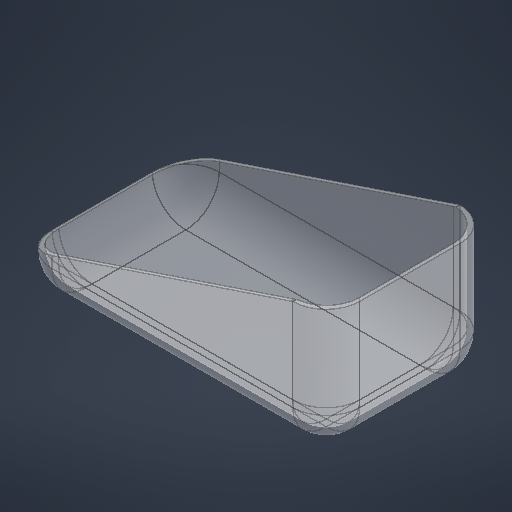
# Autodesk Inventor part: box
Saved by Autodesk Inventor 2026.2 (Build 302298010, 298A)
## iProperties
Created: 2026-04-03
Part Number: box
Material: ABS 플라스틱
Document SubType Name: Modeling
Designer: work
Density: 1.06 g/cm^3
Appearance: 선명 - 밝음
Author: work
Autodesk Inventor part; units mm, degrees
ref_plane "YZ Plane" through (0, 0, 0) normal (1, 0, 0) x (0, 1, 0)
ref_plane "XZ Plane" through (0, 0, 0) normal (0, 1, 0) x (-1, 0, 0)
ref_plane "XY Plane" through (0, 0, 0) normal (0, 0, 1) x (1, 0, 0)
sketch "스케치1" plane through (0, 0, 0) normal (1, 0, 0) x (0, 1, 0)
  line L0 (0, 0) -> (75, 0)
  line L1 (75, 0) -> (75, -100)
  line L2 (75, -100) -> (0, -100)
  line L3 (0, -100) -> (0, 0)
  line L4 (75, -2) -> (2, -2)
  line L5 (2, -2) -> (2, -98)
  line L6 (2, -98) -> (75, -98)
  line L7 (75, -98) -> (75, -2)
  point P0 (75, -50)
  point P1 (75, -98)
  dimension "d0" = 75
  dimension "d1" = 100
  dimension "d2" = 2
  dimension "d3" = 2
  constraints: 16 end point, 4 parallel, 2 horizontal, 2 midpoint, 2 perpendicular, 1 point on line
  measures "d0" distance of L1.end L2.end
  measures "d1" distance of L0.end L1.end
  measures "d2" distance between parallel lines of L0 L4
  measures "d3" distance between parallel lines of L3 L5
extrude "돌출1" add sketch "스케치1" along normal blind 180 contours L0 L1 L4 L5 L6 L2 L3
sketch "스케치2" plane through (0, 0, 0) normal (-1, 0, 0) x (0, 0, 1)
  line L0 (0, 0) -> (-100, 0) projected
  line L1 (-2, 75) -> (0, 75) projected
  line L2 (-100, 0) -> (0, 0)
  line L3 (0, 0) -> (0, 75)
  line L4 (0, 75) -> (-100, 75)
  line L5 (-100, 75) -> (-100, 0)
  constraints: 8 end point, 2 parallel, 1 horizontal, 1 perpendicular
extrude "돌출2" add sketch "스케치2" along normal blind 2
sketch "스케치3" plane through (180, 0, 0) normal (1, 0, 0) x (0, 0, -1)
  line L0 (100, 75) -> (100, 0) projected
  line L1 (0, 0) -> (100, 0)
  line L2 (100, 0) -> (100, 75)
  line L3 (100, 75) -> (0, 75)
  line L4 (0, 75) -> (0, 0)
  constraints: 8 end point, 2 parallel, 1 horizontal, 1 perpendicular
extrude "돌출3" add sketch "스케치3" along normal blind 2
fillet "모깎기1" radius 20 8 edges at (182, 37.5, 0) (180, 38.5, -2) (0, 38.5, -2) (0, 38.5, -98) (-2, 37.5, -100) (180, 38.5, -98) (182, 37.5, -100) (-2, 37.5, 0)
fillet "모깎기2" radius 20 16 edges at (174.1421, 2, -7.8579) (180, 2, -50) (174.1421, 2, -92.1421) (90, 2, -98) (5.8579, 2, -92.1421) (0, 2, -50) (5.8579, 2, -7.8579) (90, 2, -2) (176.1421, 0, -94.1421) (90, 0, -100) (3.8579, 0, -94.1421) (-2, 0, -50) (3.8579, 0, -5.8579) (90, 0, 0) (176.1421, 0, -5.8579) (182, 0, -50)
sketch "스케치4" plane through (162, 75, -100) normal (0, 0, -1) x (-1, 0, 0)
  line L0 (2, 0) -> (-18, 0) projected
  line L1 (164, 0) -> (164, -55) projected
  line L2 (-0.0918, 0) -> (164, -55)
  line L3 (144, -55) -> (0, -55) projected
  line L4 (144, 0) -> (144, -55) projected
  line L5 (144, 0) -> (0, 0) projected
  line L6 (0, -55) -> (0, 0) projected
  line L7 (164, -55) -> (144, -55) projected
  line L8 (164, -55) -> (164, 0) projected
  line L9 (164, 0) -> (144, 0) projected
  line L10 (144, 0) -> (144, -55) projected
  point P0 (162, -75)
  point P1 (0, -0.0308)
  constraints: 2 end point, 1 point on line
extrude "돌출4" cut sketch "스케치4" against normal through all contours L5 L4 L2 L6 L0 | L9 L1 L2 L4
